CBP-0000-RevE-CAD-checkpoint006 (Autodesk Fusion 360 design; units mm, degrees)
part number: 2026-09-21-21-13-08-575
part number: 2026-09-22-14-43-03-767
part number: 2026-09-22-14-43-32-423
part number: 2026-09-22-14-58-32-491
part number: 2026-09-22-14-58-32-570
part number: 2026-09-22-14-58-32-641
part number: 2026-09-22-14-58-32-649
part number: 2026-09-22-14-58-32-656
part number: 2026-09-22-14-58-32-663
part number: 2026-09-22-14-58-32-671
part number: 2026-09-22-14-58-32-679
part number: 2026-09-22-14-58-32-687
part number: 2026-09-22-14-58-32-694
part number: 2026-09-22-14-58-32-777
part number: 2026-09-22-14-58-32-866
part number: 2026-09-22-15-02-12-520
part number: 2026-09-22-15-02-12-611
part number: 2026-09-22-15-02-12-705
part number: 2026-09-22-15-02-12-797
part number: 2026-09-22-15-02-12-894
part number: 2026-09-22-15-04-06-454
part number: 2026-09-22-15-34-02-991
part number: 2026-09-22-15-34-03-274
part number: 2026-09-22-15-34-03-552
Autodesk Fusion 360 part; units mm, degrees
(part 1 of 2)
sketch "SK-1100-01_BASE_OUTLINE_PARAMETRIC" plane through (0, 0, 0) normal (0, 1, 0) x (1, 0, 0) in component "CBP-1100_BASE_PLATE"
  line L0 (150, 130) -> (-150, 130)
  line L1 (-150, 130) -> (-150, -130)
  line L2 (-150, -130) -> (150, -130)
  line L3 (150, -130) -> (150, 130)
  line L4 (150, 130) -> (-150, -130) construction
  line L5 (-150, 130) -> (150, -130) construction
  dimension "d4" = 300
  dimension "d5" = 260
  constraint horizontal L0
  constraint perpendicular L0 L1
  constraint parallel L0 L2
  constraint parallel L1 L3
  constraint coincident L4 origin
  constraint coincident L5 origin
  measures "d4" distance of L0.start L0.end
  measures "d5" distance of L0 L2
extrude "EX-1100-01_BASE_STOCK" add sketch "SK-1100-01_BASE_OUTLINE_PARAMETRIC" along normal blind 12 makes body 1 in component "CBP-1100_BASE_PLATE"
sketch "SK-1100-02_CLEARANCE_APERTURE" plane through (0, 0, 0) normal (0, 1, 0) x (1, 0, 0) in component "CBP-1100_BASE_PLATE"
  line L0 (74, 49) -> (-74, 49)
  line L1 (-74, 49) -> (-74, -49)
  line L2 (-74, -49) -> (74, -49)
  line L3 (74, -49) -> (74, 49)
  dimension "d56" = 148
  dimension "d57" = 98
  dimension "d58" = 74
  dimension "d59" = 49
  constraint horizontal L0
  constraint vertical L1
  constraint horizontal L2
  constraint vertical L3
  measures "d56" horizontal distance of L0.start L0.end
  measures "d57" vertical distance of L0.end L1.end
  measures "d58" horizontal distance of origin L0.start
  measures "d59" vertical distance of origin L0.start
extrude "CUT-1100-01_BED_SWEEP_APERTURE" cut sketch "SK-1100-02_CLEARANCE_APERTURE" along normal blind 12 bodies 1 in component "CBP-1100_BASE_PLATE"
sketch "SK-1100-03_FOUR_BASE_MOUNTS" plane through (0, 0, 0) normal (0, 1, 0) x (1, 0, 0) in component "CBP-1100_BASE_PLATE"
  circle A0 centre (-130, -110) radius 4.5
  circle A1 centre (-130, 110) radius 4.5
  circle A2 centre (130, -110) radius 4.5
  circle A3 centre (130, 110) radius 4.5
  dimension "d62" = 130
  dimension "d63" = 110
  dimension "d64" = 9
  dimension "d65" = 110
  dimension "d66" = 130
  constraint vertical A0.centre A1.centre
  constraint equal A0 A1
  constraint horizontal A0.centre A2.centre
  constraint equal A0 A2
  constraint vertical A2.centre A3.centre
  constraint horizontal A1.centre A3.centre
  constraint equal A0 A3
  measures "d62" horizontal distance of origin A0.centre
  measures "d63" vertical distance of origin A0.centre
  measures "d64" diameter of A0
  measures "d65" vertical distance of origin A1.centre
  measures "d66" horizontal distance of origin A2.centre
extrude "CUT-1100-02_FOUR_M8_MOUNTS" cut sketch "SK-1100-03_FOUR_BASE_MOUNTS" along normal blind 12 bodies 1 in component "CBP-1100_BASE_PLATE"
sketch "SK-1200-01_COLUMN_SECTION" plane through (0, 0, 0) normal (0, 1, 0) x (1, 0, 0) in component "CBP-1200_40MM_Z_COLUMN"
  line L0 (20, 20) -> (-20, 20)
  line L1 (-20, 20) -> (-20, -20)
  line L2 (-20, -20) -> (20, -20)
  line L3 (20, -20) -> (20, 20)
  dimension "d69" = 40
  dimension "d70" = 40
  dimension "d71" = 20
  dimension "d72" = 20
  constraint horizontal L0
  constraint vertical L1
  constraint horizontal L2
  constraint vertical L3
  measures "d69" horizontal distance of L0.start L0.end
  measures "d70" vertical distance of L0.end L1.end
  measures "d71" horizontal distance of origin L0.start
  measures "d72" vertical distance of origin L0.start
extrude "EX-CBP-1200_COLUMN_ENVELOPE" add sketch "SK-1200-01_COLUMN_SECTION" along normal blind 180 separate body makes body 2 in component "CBP-1200_40MM_Z_COLUMN"
sketch "SK-1210-01_BEAM_SECTION" plane through (0, 0, 0) normal (0, 1, 0) x (1, 0, 0) in component "CBP-1210_Z_CROSSBEAM_ENVELOPE"
  line L0 (110, 20) -> (-110, 20)
  line L1 (-110, 20) -> (-110, -20)
  line L2 (-110, -20) -> (110, -20)
  line L3 (110, -20) -> (110, 20)
  dimension "d75" = 220
  dimension "d76" = 40
  dimension "d77" = 110
  dimension "d78" = 20
  constraint horizontal L0
  constraint vertical L1
  constraint horizontal L2
  constraint vertical L3
  measures "d75" horizontal distance of L0.start L0.end
  measures "d76" vertical distance of L0.end L1.end
  measures "d77" horizontal distance of origin L0.start
  measures "d78" vertical distance of origin L0.start
extrude "EX-CBP-1210_CROSSBEAM_ENVELOPE" add sketch "SK-1210-01_BEAM_SECTION" along normal blind 40 separate body makes body 3 in component "CBP-1210_Z_CROSSBEAM_ENVELOPE"
sketch "SK-2100-01_STAGE_OUTLINE" plane through (0, 0, 0) normal (0, 1, 0) x (1, 0, 0) in component "CBP-2100_CARBON_XY_STAGE"
  line L0 (56, 42) -> (-56, 42)
  line L1 (-56, 42) -> (-56, -42)
  line L2 (-56, -42) -> (56, -42)
  line L3 (56, -42) -> (56, 42)
  dimension "d81" = 112
  dimension "d82" = 84
  dimension "d83" = 56
  dimension "d84" = 42
  constraint horizontal L0
  constraint vertical L1
  constraint horizontal L2
  constraint vertical L3
  measures "d81" horizontal distance of L0.start L0.end
  measures "d82" vertical distance of L0.end L1.end
  measures "d83" horizontal distance of origin L0.start
  measures "d84" vertical distance of origin L0.start
extrude "EX-CBP-2100_2MM_STAGE_STOCK" add sketch "SK-2100-01_STAGE_OUTLINE" along normal blind 2 separate body makes body 4 in component "CBP-2100_CARBON_XY_STAGE"
sketch "SK-3100-01_BED_OUTLINE" plane through (0, 0, 0) normal (0, 1, 0) x (1, 0, 0) in component "CBP-3100_BED_SUBSTRATE"
  line L0 (38, 25) -> (-38, 25)
  line L1 (-38, 25) -> (-38, -25)
  line L2 (-38, -25) -> (38, -25)
  line L3 (38, -25) -> (38, 25)
  dimension "d87" = 76
  dimension "d88" = 50
  dimension "d89" = 38
  dimension "d90" = 25
  constraint horizontal L0
  constraint vertical L1
  constraint horizontal L2
  constraint vertical L3
  measures "d87" horizontal distance of L0.start L0.end
  measures "d88" vertical distance of L0.end L1.end
  measures "d89" horizontal distance of origin L0.start
  measures "d90" vertical distance of origin L0.start
extrude "EX-CBP-3100_BED_SUBSTRATE_STOCK" add sketch "SK-3100-01_BED_OUTLINE" along normal blind 3 separate body makes body 5 in component "CBP-3100_BED_SUBSTRATE"
sketch "SK-3110-01_SURFACE_OUTLINE" plane through (0, 0, 0) normal (0, 1, 0) x (1, 0, 0) in component "CBP-3110_BUILD_SURFACE"
  line L0 (38, 25) -> (-38, 25)
  line L1 (-38, 25) -> (-38, -25)
  line L2 (-38, -25) -> (38, -25)
  line L3 (38, -25) -> (38, 25)
  dimension "d93" = 76
  dimension "d94" = 50
  dimension "d95" = 38
  dimension "d96" = 25
  constraint horizontal L0
  constraint vertical L1
  constraint horizontal L2
  constraint vertical L3
  measures "d93" horizontal distance of L0.start L0.end
  measures "d94" vertical distance of L0.end L1.end
  measures "d95" horizontal distance of origin L0.start
  measures "d96" vertical distance of origin L0.start
extrude "EX-CBP-3110_BUILD_SURFACE_FILM" add sketch "SK-3110-01_SURFACE_OUTLINE" along normal blind 0.25 separate body makes body 6 in component "CBP-3110_BUILD_SURFACE"
sketch "SK-P201-01_X_RAIL_ENVELOPE" plane through (0, 0, 0) normal (0, 1, 0) x (1, 0, 0) in component "CBP-P201_MGN7_X_RAIL_130_PROXY"
  line L0 (65, 3.5) -> (-65, 3.5)
  line L1 (-65, 3.5) -> (-65, -3.5)
  line L2 (-65, -3.5) -> (65, -3.5)
  line L3 (65, -3.5) -> (65, 3.5)
  dimension "d110" = 130
  dimension "d111" = 7
  dimension "d112" = 65
  dimension "d113" = 3.5
  constraint horizontal L0
  constraint vertical L1
  constraint horizontal L2
  constraint vertical L3
  measures "d110" horizontal distance of L0.start L0.end
  measures "d111" vertical distance of L0.end L1.end
  measures "d112" horizontal distance of origin L0.start
  measures "d113" vertical distance of origin L0.start
extrude "EX-CBP-P201_X_RAIL_ENVELOPE" add sketch "SK-P201-01_X_RAIL_ENVELOPE" along normal blind 4.8 separate body makes body 7 in component "CBP-P201_MGN7_X_RAIL_130_PROXY"
sketch "SK-P202-01_X_BLOCK_CAP" plane through (0, 0, 0) normal (0, 1, 0) x (1, 0, 0) in component "CBP-P202_MGN7H_X_BLOCK_PROXY"
  line L0 (15.4, 8.5) -> (-15.4, 8.5)
  line L1 (-15.4, 8.5) -> (-15.4, -8.5)
  line L2 (-15.4, -8.5) -> (15.4, -8.5)
  line L3 (15.4, -8.5) -> (15.4, 8.5)
  dimension "d116" = 30.8
  dimension "d117" = 17
  dimension "d118" = 15.4
  dimension "d119" = 8.5
  constraint horizontal L0
  constraint vertical L1
  constraint horizontal L2
  constraint vertical L3
  measures "d116" horizontal distance of L0.start L0.end
  measures "d117" vertical distance of L0.end L1.end
  measures "d118" horizontal distance of origin L0.start
  measures "d119" vertical distance of origin L0.start
extrude "EX-CBP-P202_X_BLOCK_UPPER_ENVELOPE" add sketch "SK-P202-01_X_BLOCK_CAP" along normal blind 3.2 separate body makes body 8 in component "CBP-P202_MGN7H_X_BLOCK_PROXY"
sketch "SK-2200-01_BRIDGE_ENVELOPE" plane through (0, 0, 0) normal (0, 1, 0) x (1, 0, 0) in component "CBP-2200_CARBON_X_BRIDGE"
  line L0 (5, 70) -> (-5, 70)
  line L1 (-5, 70) -> (-5, -70)
  line L2 (-5, -70) -> (5, -70)
  line L3 (5, -70) -> (5, 70)
  dimension "d122" = 10
  dimension "d123" = 140
  dimension "d124" = 5
  dimension "d125" = 70
  constraint horizontal L0
  constraint vertical L1
  constraint horizontal L2
  constraint vertical L3
  measures "d122" horizontal distance of L0.start L0.end
  measures "d123" vertical distance of L0.end L1.end
  measures "d124" horizontal distance of origin L0.start
  measures "d125" vertical distance of origin L0.start
extrude "EX-CBP-2200_BRIDGE_STOCK" add sketch "SK-2200-01_BRIDGE_ENVELOPE" along normal blind 10 separate body makes body 9 in component "CBP-2200_CARBON_X_BRIDGE"
sketch "SK-P203-01_Y_RAIL_ENVELOPE" plane through (0, 0, 0) normal (0, 1, 0) x (1, 0, 0) in component "CBP-P203_MGN7_Y_RAIL_110_PROXY"
  line L0 (3.5, 55) -> (-3.5, 55)
  line L1 (-3.5, 55) -> (-3.5, -55)
  line L2 (-3.5, -55) -> (3.5, -55)
  line L3 (3.5, -55) -> (3.5, 55)
  dimension "d128" = 7
  dimension "d129" = 110
  dimension "d130" = 3.5
  dimension "d131" = 55
  constraint horizontal L0
  constraint vertical L1
  constraint horizontal L2
  constraint vertical L3
  measures "d128" horizontal distance of L0.start L0.end
  measures "d129" vertical distance of L0.end L1.end
  measures "d130" horizontal distance of origin L0.start
  measures "d131" vertical distance of origin L0.start
extrude "EX-CBP-P203_Y_RAIL_ENVELOPE" add sketch "SK-P203-01_Y_RAIL_ENVELOPE" along normal blind 4.8 separate body makes body 10 in component "CBP-P203_MGN7_Y_RAIL_110_PROXY"
sketch "SK-P204-01_Y_BLOCK_CAP" plane through (0, 0, 0) normal (0, 1, 0) x (1, 0, 0) in component "CBP-P204_MGN7H_Y_BLOCK_PROXY"
  line L0 (8.5, 15.4) -> (-8.5, 15.4)
  line L1 (-8.5, 15.4) -> (-8.5, -15.4)
  line L2 (-8.5, -15.4) -> (8.5, -15.4)
  line L3 (8.5, -15.4) -> (8.5, 15.4)
  dimension "d134" = 17
  dimension "d135" = 30.8
  dimension "d136" = 8.5
  dimension "d137" = 15.4
  constraint horizontal L0
  constraint vertical L1
  constraint horizontal L2
  constraint vertical L3
  measures "d134" horizontal distance of L0.start L0.end
  measures "d135" vertical distance of L0.end L1.end
  measures "d136" horizontal distance of origin L0.start
  measures "d137" vertical distance of origin L0.start
extrude "EX-CBP-P204_Y_BLOCK_UPPER_ENVELOPE" add sketch "SK-P204-01_Y_BLOCK_CAP" along normal blind 3.2 separate body makes body 11 in component "CBP-P204_MGN7H_Y_BLOCK_PROXY"
sketch "SK-1300-01_SHIM_OUTLINE" plane through (0, 0, 0) normal (0, 1, 0) x (1, 0, 0) in component "CBP-1300_X_RAIL_ALIGNMENT_SHIM"
  line L0 (65, 6) -> (-65, 6)
  line L1 (-65, 6) -> (-65, -6)
  line L2 (-65, -6) -> (65, -6)
  line L3 (65, -6) -> (65, 6)
  dimension "d142" = 130
  dimension "d143" = 12
  dimension "d144" = 65
  dimension "d145" = 6
  constraint horizontal L0
  constraint vertical L1
  constraint horizontal L2
  constraint vertical L3
  measures "d142" horizontal distance of L0.start L0.end
  measures "d143" vertical distance of L0.end L1.end
  measures "d144" horizontal distance of origin L0.start
  measures "d145" vertical distance of origin L0.start
extrude "EX-CBP-1300_SHIM_STOCK" add sketch "SK-1300-01_SHIM_OUTLINE" along normal blind 2 separate body makes body 12 in component "CBP-1300_X_RAIL_ALIGNMENT_SHIM"
sketch "SK-P201-02_NINE_MGN7_MOUNT_HOLES" plane through (0, 0, 0) normal (0, 1, 0) x (1, 0, 0) in component "CBP-P201_MGN7_X_RAIL_130_PROXY"
  circle A0 centre (-60, 0) radius 1.15
  circle A1 centre (-45, 0) radius 1.15
  circle A2 centre (-30, 0) radius 1.15
  circle A3 centre (-15, 0) radius 1.15
  circle A4 centre (0, 0) radius 1.15
  circle A5 centre (15, 0) radius 1.15
  circle A6 centre (30, 0) radius 1.15
  circle A7 centre (45, 0) radius 1.15
  circle A8 centre (60, 0) radius 1.15
  dimension "d151" = 60
  dimension "d152" = 2.3
  dimension "d153" = 45
  dimension "d154" = 2.3
  dimension "d155" = 30
  dimension "d156" = 2.3
  dimension "d157" = 15
  dimension "d158" = 2.3
  dimension "d159" = 2.3
  dimension "d160" = 15
  dimension "d161" = 2.3
  dimension "d162" = 30
  dimension "d163" = 2.3
  dimension "d164" = 45
  dimension "d165" = 2.3
  dimension "d166" = 60
  dimension "d167" = 2.3
  constraint horizontal A4.centre A0.centre
  constraint horizontal A4.centre A1.centre
  constraint horizontal A4.centre A2.centre
  constraint horizontal A4.centre A3.centre
  constraint coincident A4.centre origin
  constraint horizontal A4.centre A5.centre
  constraint horizontal A4.centre A6.centre
  constraint horizontal A4.centre A7.centre
  constraint horizontal A4.centre A8.centre
  measures "d151" horizontal distance of A4.centre A0.centre
  measures "d152" diameter of A0
  measures "d153" horizontal distance of A4.centre A1.centre
  measures "d154" diameter of A1
  measures "d155" horizontal distance of A4.centre A2.centre
  measures "d156" diameter of A2
  measures "d157" horizontal distance of A4.centre A3.centre
  measures "d158" diameter of A3
  measures "d159" diameter of A4
  measures "d160" horizontal distance of A4.centre A5.centre
  measures "d161" diameter of A5
  measures "d162" horizontal distance of A4.centre A6.centre
  measures "d163" diameter of A6
  measures "d164" horizontal distance of A4.centre A7.centre
  measures "d165" diameter of A7
  measures "d166" horizontal distance of A4.centre A8.centre
  measures "d167" diameter of A8
extrude "CUT-MGN7-THROUGH-HOLES" cut sketch "SK-P201-02_NINE_MGN7_MOUNT_HOLES" along normal blind 4.8 bodies 7 in component "CBP-P201_MGN7_X_RAIL_130_PROXY"
sketch "SK-P203-02_SEVEN_MGN7_MOUNT_HOLES" plane through (0, 0, 0) normal (0, 1, 0) x (1, 0, 0) in component "CBP-P203_MGN7_Y_RAIL_110_PROXY"
  circle A0 centre (0, -45) radius 1.15
  circle A1 centre (0, -30) radius 1.15
  circle A2 centre (0, -15) radius 1.15
  circle A3 centre (0, 0) radius 1.15
  circle A4 centre (0, 15) radius 1.15
  circle A5 centre (0, 30) radius 1.15
  circle A6 centre (0, 45) radius 1.15
  dimension "d170" = 45
  dimension "d171" = 2.3
  dimension "d172" = 30
  dimension "d173" = 2.3
  dimension "d174" = 15
  dimension "d175" = 2.3
  dimension "d176" = 2.3
  dimension "d177" = 15
  dimension "d178" = 2.3
  dimension "d179" = 30
  dimension "d180" = 2.3
  dimension "d181" = 45
  dimension "d182" = 2.3
  constraint vertical A3.centre A0.centre
  constraint vertical A3.centre A1.centre
  constraint vertical A3.centre A2.centre
  constraint coincident A3.centre origin
  constraint vertical A3.centre A4.centre
  constraint vertical A3.centre A5.centre
  constraint vertical A3.centre A6.centre
  measures "d170" vertical distance of A3.centre A0.centre
  measures "d171" diameter of A0
  measures "d172" vertical distance of A3.centre A1.centre
  measures "d173" diameter of A1
  measures "d174" vertical distance of A3.centre A2.centre
  measures "d175" diameter of A2
  measures "d176" diameter of A3
  measures "d177" vertical distance of A3.centre A4.centre
  measures "d178" diameter of A4
  measures "d179" vertical distance of A3.centre A5.centre
  measures "d180" diameter of A5
  measures "d181" vertical distance of A3.centre A6.centre
  measures "d182" diameter of A6
extrude "CUT-MGN7-THROUGH-HOLES'" cut sketch "SK-P203-02_SEVEN_MGN7_MOUNT_HOLES" along normal blind 4.8 bodies 10 in component "CBP-P203_MGN7_Y_RAIL_110_PROXY"
sketch "SK-P201-03_NINE_MGN7_COUNTERBORES" plane through (0, 4.8, 0) normal (0, 1, 0) x (0, 0, 1) in component "CBP-P201_MGN7_X_RAIL_130_PROXY"
  line L0 (3.5, 65) -> (-3.5, 65)
  line L1 (-3.5, 65) -> (-3.5, -65)
  line L2 (-3.5, -65) -> (3.5, -65)
  line L3 (3.5, -65) -> (3.5, 65)
  circle A0 centre (0, 60) radius 1.15
  circle A1 centre (0, 30) radius 1.15
  circle A2 centre (0, -60) radius 1.15
  circle A3 centre (0, -15) radius 1.15
  circle A4 centre (0, -45) radius 1.15
  circle A5 centre (0, -30) radius 1.15
  circle A6 centre (0, 0) radius 1.15
  circle A7 centre (0, 15) radius 1.15
  circle A8 centre (0, 45) radius 1.15
  circle A9 centre (0, -60) radius 2.1
  circle A10 centre (0, -45) radius 2.1
  circle A11 centre (0, -30) radius 2.1
  circle A12 centre (0, -15) radius 2.1
  circle A13 centre (0, 0) radius 2.1
  circle A14 centre (0, 15) radius 2.1
  circle A15 centre (0, 30) radius 2.1
  circle A16 centre (0, 45) radius 2.1
  circle A17 centre (0, 60) radius 2.1
  dimension "d187" = 60
  dimension "d188" = 4.2
  dimension "d189" = 45
  dimension "d190" = 4.2
  dimension "d191" = 30
  dimension "d192" = 4.2
  dimension "d193" = 15
  dimension "d194" = 4.2
  dimension "d195" = 4.2
  dimension "d196" = 15
  dimension "d197" = 4.2
  dimension "d198" = 30
  dimension "d199" = 4.2
  dimension "d200" = 45
  dimension "d201" = 4.2
  dimension "d202" = 60
  dimension "d203" = 4.2
  constraint vertical A6.centre A2.centre
  constraint vertical A6.centre A4.centre
  constraint vertical A6.centre A5.centre
  constraint vertical A6.centre A3.centre
  constraint coincident A6.centre A13.centre
  constraint vertical A6.centre A7.centre
  constraint vertical A6.centre A1.centre
  constraint vertical A6.centre A8.centre
  constraint vertical A6.centre A0.centre
  measures "d187" vertical distance of A6.centre A2.centre
  measures "d188" diameter of A9
  measures "d189" vertical distance of A6.centre A4.centre
  measures "d190" diameter of A10
  measures "d191" vertical distance of A6.centre A5.centre
  measures "d192" diameter of A11
  measures "d193" vertical distance of A6.centre A3.centre
  measures "d194" diameter of A12
  measures "d195" diameter of A13
  measures "d196" vertical distance of A6.centre A7.centre
  measures "d197" diameter of A14
  measures "d198" vertical distance of A6.centre A1.centre
  measures "d199" diameter of A15
  measures "d200" vertical distance of A6.centre A8.centre
  measures "d201" diameter of A16
  measures "d202" vertical distance of A6.centre A0.centre
  measures "d203" diameter of A17
sketch "SK-P203-03_SEVEN_MGN7_COUNTERBORES" plane through (0, 4.8, 0) normal (0, 1, 0) x (0, 0, 1) in component "CBP-P203_MGN7_Y_RAIL_110_PROXY"
  line L0 (55, 3.5) -> (-55, 3.5)
  line L1 (-55, 3.5) -> (-55, -3.5)
  line L2 (-55, -3.5) -> (55, -3.5)
  line L3 (55, -3.5) -> (55, 3.5)
  circle A0 centre (-45, 0) radius 1.15
  circle A1 centre (-15, 0) radius 1.15
  circle A2 centre (0, 0) radius 1.15
  circle A3 centre (30, 0) radius 1.15
  circle A4 centre (15, 0) radius 1.15
  circle A5 centre (45, 0) radius 1.15
  circle A6 centre (-30, 0) radius 1.15
  circle A7 centre (-45, 0) radius 2.1
  circle A8 centre (-30, 0) radius 2.1
  circle A9 centre (-15, 0) radius 2.1
  circle A10 centre (0, 0) radius 2.1
  circle A11 centre (15, 0) radius 2.1
  circle A12 centre (30, 0) radius 2.1
  circle A13 centre (45, 0) radius 2.1
  dimension "d206" = 45
  dimension "d207" = 4.2
  dimension "d208" = 30
  dimension "d209" = 4.2
  dimension "d210" = 15
  dimension "d211" = 4.2
  dimension "d212" = 4.2
  dimension "d213" = 15
  dimension "d214" = 4.2
  dimension "d215" = 30
  dimension "d216" = 4.2
  dimension "d217" = 45
  dimension "d218" = 4.2
  constraint horizontal A2.centre A0.centre
  constraint horizontal A2.centre A6.centre
  constraint horizontal A2.centre A1.centre
  constraint coincident A2.centre A10.centre
  constraint horizontal A2.centre A4.centre
  constraint horizontal A2.centre A3.centre
  constraint horizontal A2.centre A5.centre
  measures "d206" horizontal distance of A2.centre A0.centre
  measures "d207" diameter of A7
  measures "d208" horizontal distance of A2.centre A6.centre
  measures "d209" diameter of A8
  measures "d210" horizontal distance of A2.centre A1.centre
  measures "d211" diameter of A9
  measures "d212" diameter of A10
  measures "d213" horizontal distance of A2.centre A4.centre
  measures "d214" diameter of A11
  measures "d215" horizontal distance of A2.centre A3.centre
  measures "d216" diameter of A12
  measures "d217" horizontal distance of A2.centre A5.centre
  measures "d218" diameter of A13
extrude "CUT-MGN7-COUNTERBORES" cut sketch "SK-P201-03_NINE_MGN7_COUNTERBORES" against normal blind 2.4 contours A9 | A10 | A11 | A12 | A13 | A14 | A15 | A16 | A17 bodies 7 in component "CBP-P201_MGN7_X_RAIL_130_PROXY"
extrude "CUT-MGN7-COUNTERBORES'" cut sketch "SK-P203-03_SEVEN_MGN7_COUNTERBORES" against normal blind 2.4 contours A7 | A8 | A9 | A10 | A11 | A12 | A13 bodies 10 in component "CBP-P203_MGN7_Y_RAIL_110_PROXY"
sketch "SK-P202-02_FOUR_M2_PILOTS_01" plane through (0, 3.2, 0) normal (0, 1, 0) x (0, 0, 1) in component "CBP-P202_MGN7H_X_BLOCK_PROXY"
  line L0 (8.5, 15.4) -> (-8.5, 15.4)
  line L1 (-8.5, 15.4) -> (-8.5, -15.4)
  line L2 (-8.5, -15.4) -> (8.5, -15.4)
  line L3 (8.5, -15.4) -> (8.5, 15.4)
  circle A0 centre (-6, -6.5) radius 0.8
  dimension "d229" = 6
  dimension "d230" = 6.5
  dimension "d231" = 1.6
  measures "d229" horizontal distance of origin A0.centre
  measures "d230" vertical distance of origin A0.centre
  measures "d231" diameter of A0
extrude "CUT-MGN7H-M2-TAP-PILOT-01" cut sketch "SK-P202-02_FOUR_M2_PILOTS_01" against normal blind 2.5 contours A0 bodies 8 in component "CBP-P202_MGN7H_X_BLOCK_PROXY"
sketch "SK-P202-02_FOUR_M2_PILOTS_02" plane through (0, 3.2, 0) normal (0, 1, 0) x (0, 0, 1) in component "CBP-P202_MGN7H_X_BLOCK_PROXY"
  circle A0 centre (-6, -6.5) radius 0.8
  line L0 (8.5, 15.4) -> (-8.5, 15.4)
  line L1 (-8.5, 15.4) -> (-8.5, -15.4)
  line L2 (-8.5, -15.4) -> (8.5, -15.4)
  line L3 (8.5, -15.4) -> (8.5, 15.4)
  circle A1 centre (6, -6.5) radius 0.8
  dimension "d234" = 6
  dimension "d235" = 6.5
  dimension "d236" = 1.6
  measures "d234" horizontal distance of origin A1.centre
  measures "d235" vertical distance of origin A1.centre
  measures "d236" diameter of A1
extrude "CUT-MGN7H-M2-TAP-PILOT-02" cut sketch "SK-P202-02_FOUR_M2_PILOTS_02" against normal blind 2.5 contours A1 bodies 8 in component "CBP-P202_MGN7H_X_BLOCK_PROXY"
sketch "SK-P202-02_FOUR_M2_PILOTS_03" plane through (0, 3.2, 0) normal (0, 1, 0) x (0, 0, 1) in component "CBP-P202_MGN7H_X_BLOCK_PROXY"
  circle A0 centre (6, -6.5) radius 0.8
  circle A1 centre (-6, -6.5) radius 0.8
  line L0 (8.5, 15.4) -> (-8.5, 15.4)
  line L1 (-8.5, 15.4) -> (-8.5, -15.4)
  line L2 (-8.5, -15.4) -> (8.5, -15.4)
  line L3 (8.5, -15.4) -> (8.5, 15.4)
  circle A2 centre (-6, 6.5) radius 0.8
  dimension "d239" = 6
  dimension "d240" = 6.5
  dimension "d241" = 1.6
  measures "d239" horizontal distance of origin A2.centre
  measures "d240" vertical distance of origin A2.centre
  measures "d241" diameter of A2
extrude "CUT-MGN7H-M2-TAP-PILOT-03" cut sketch "SK-P202-02_FOUR_M2_PILOTS_03" against normal blind 2.5 contours A2 bodies 8 in component "CBP-P202_MGN7H_X_BLOCK_PROXY"
sketch "SK-P202-02_FOUR_M2_PILOTS_04" plane through (0, 3.2, 0) normal (0, 1, 0) x (0, 0, 1) in component "CBP-P202_MGN7H_X_BLOCK_PROXY"
  circle A0 centre (-6, 6.5) radius 0.8
  circle A1 centre (6, -6.5) radius 0.8
  circle A2 centre (-6, -6.5) radius 0.8
  line L0 (8.5, 15.4) -> (-8.5, 15.4)
  line L1 (-8.5, 15.4) -> (-8.5, -15.4)
  line L2 (-8.5, -15.4) -> (8.5, -15.4)
  line L3 (8.5, -15.4) -> (8.5, 15.4)
  circle A3 centre (6, 6.5) radius 0.8
  dimension "d244" = 6
  dimension "d245" = 6.5
  dimension "d246" = 1.6
  measures "d244" horizontal distance of origin A3.centre
  measures "d245" vertical distance of origin A3.centre
  measures "d246" diameter of A3
extrude "CUT-MGN7H-M2-TAP-PILOT-04" cut sketch "SK-P202-02_FOUR_M2_PILOTS_04" against normal blind 2.5 contours A3 bodies 8 in component "CBP-P202_MGN7H_X_BLOCK_PROXY"
sketch "SK-P204-02_FOUR_M2_PILOTS_01" plane through (0, 3.2, 0) normal (0, 1, 0) x (0, 0, 1) in component "CBP-P204_MGN7H_Y_BLOCK_PROXY"
  line L0 (15.4, 8.5) -> (-15.4, 8.5)
  line L1 (-15.4, 8.5) -> (-15.4, -8.5)
  line L2 (-15.4, -8.5) -> (15.4, -8.5)
  line L3 (15.4, -8.5) -> (15.4, 8.5)
  circle A0 centre (-6.5, -6) radius 0.8
  dimension "d249" = 6.5
  dimension "d250" = 6
  dimension "d251" = 1.6
  measures "d249" horizontal distance of origin A0.centre
  measures "d250" vertical distance of origin A0.centre
  measures "d251" diameter of A0
extrude "CUT-MGN7H-M2-TAP-PILOT-01'" cut sketch "SK-P204-02_FOUR_M2_PILOTS_01" against normal blind 2.5 contours A0 bodies 11 in component "CBP-P204_MGN7H_Y_BLOCK_PROXY"
sketch "SK-P204-02_FOUR_M2_PILOTS_02" plane through (0, 3.2, 0) normal (0, 1, 0) x (0, 0, 1) in component "CBP-P204_MGN7H_Y_BLOCK_PROXY"
  circle A0 centre (-6.5, -6) radius 0.8
  line L0 (15.4, 8.5) -> (-15.4, 8.5)
  line L1 (-15.4, 8.5) -> (-15.4, -8.5)
  line L2 (-15.4, -8.5) -> (15.4, -8.5)
  line L3 (15.4, -8.5) -> (15.4, 8.5)
  circle A1 centre (6.5, -6) radius 0.8
  dimension "d254" = 6.5
  dimension "d255" = 6
  dimension "d256" = 1.6
  measures "d254" horizontal distance of origin A1.centre
  measures "d255" vertical distance of origin A1.centre
  measures "d256" diameter of A1
extrude "CUT-MGN7H-M2-TAP-PILOT-02'" cut sketch "SK-P204-02_FOUR_M2_PILOTS_02" against normal blind 2.5 contours A1 bodies 11 in component "CBP-P204_MGN7H_Y_BLOCK_PROXY"
sketch "SK-P204-02_FOUR_M2_PILOTS_03" plane through (0, 3.2, 0) normal (0, 1, 0) x (0, 0, 1) in component "CBP-P204_MGN7H_Y_BLOCK_PROXY"
  circle A0 centre (6.5, -6) radius 0.8
  circle A1 centre (-6.5, -6) radius 0.8
  line L0 (15.4, 8.5) -> (-15.4, 8.5)
  line L1 (-15.4, 8.5) -> (-15.4, -8.5)
  line L2 (-15.4, -8.5) -> (15.4, -8.5)
  line L3 (15.4, -8.5) -> (15.4, 8.5)
  circle A2 centre (-6.5, 6) radius 0.8
  dimension "d259" = 6.5
  dimension "d260" = 6
  dimension "d261" = 1.6
  measures "d259" horizontal distance of origin A2.centre
  measures "d260" vertical distance of origin A2.centre
  measures "d261" diameter of A2
extrude "CUT-MGN7H-M2-TAP-PILOT-03'" cut sketch "SK-P204-02_FOUR_M2_PILOTS_03" against normal blind 2.5 contours A2 bodies 11 in component "CBP-P204_MGN7H_Y_BLOCK_PROXY"
sketch "SK-P204-02_FOUR_M2_PILOTS_04" plane through (0, 3.2, 0) normal (0, 1, 0) x (0, 0, 1) in component "CBP-P204_MGN7H_Y_BLOCK_PROXY"
  circle A0 centre (-6.5, 6) radius 0.8
  circle A1 centre (6.5, -6) radius 0.8
  circle A2 centre (-6.5, -6) radius 0.8
  line L0 (15.4, 8.5) -> (-15.4, 8.5)
  line L1 (-15.4, 8.5) -> (-15.4, -8.5)
  line L2 (-15.4, -8.5) -> (15.4, -8.5)
  line L3 (15.4, -8.5) -> (15.4, 8.5)
  circle A3 centre (6.5, 6) radius 0.8
  dimension "d264" = 6.5
  dimension "d265" = 6
  dimension "d266" = 1.6
  measures "d264" horizontal distance of origin A3.centre
  measures "d265" vertical distance of origin A3.centre
  measures "d266" diameter of A3
extrude "CUT-MGN7H-M2-TAP-PILOT-04'" cut sketch "SK-P204-02_FOUR_M2_PILOTS_04" against normal blind 2.5 contours A3 bodies 11 in component "CBP-P204_MGN7H_Y_BLOCK_PROXY"
sketch "SK-2200-02_END_PAD_A" plane through (0, 0, 0) normal (0, 1, 0) x (1, 0, 0) in component "CBP-2200_CARBON_X_BRIDGE"
  line L0 (11, -72) -> (-11, -72)
  line L1 (-11, -72) -> (-11, -48)
  line L2 (-11, -48) -> (11, -48)
  line L3 (11, -48) -> (11, -72)
  dimension "d271" = 22
  dimension "d272" = 24
  dimension "d273" = 11
  dimension "d274" = 72
  constraint horizontal L0
  constraint vertical L1
  constraint horizontal L2
  constraint vertical L3
  measures "d271" horizontal distance of L0.start L0.end
  measures "d272" vertical distance of L0.end L1.end
  measures "d273" horizontal distance of origin L0.start
  measures "d274" vertical distance of origin L0.start
extrude "JOIN-BRIDGE-END-PAD-A" add sketch "SK-2200-02_END_PAD_A" along normal blind 10 bodies 9 in component "CBP-2200_CARBON_X_BRIDGE"
sketch "SK-2200-02_END_PAD_B" plane through (0, 0, 0) normal (0, 1, 0) x (1, 0, 0) in component "CBP-2200_CARBON_X_BRIDGE"
  line L0 (11, 72) -> (-11, 72)
  line L1 (-11, 72) -> (-11, 48)
  line L2 (-11, 48) -> (11, 48)
  line L3 (11, 48) -> (11, 72)
  dimension "d277" = 22
  dimension "d278" = 24
  dimension "d279" = 11
  dimension "d280" = 72
  constraint horizontal L0
  constraint vertical L1
  constraint horizontal L2
  constraint vertical L3
  measures "d277" horizontal distance of L0.start L0.end
  measures "d278" vertical distance of L0.end L1.end
  measures "d279" horizontal distance of origin L0.start
  measures "d280" vertical distance of origin L0.start
extrude "JOIN-BRIDGE-END-PAD-B" add sketch "SK-2200-02_END_PAD_B" along normal blind 10 bodies 9 in component "CBP-2200_CARBON_X_BRIDGE"
sketch "SK-2200-03_M2_XBLOCK_CLEAR_01" plane through (0, 0, 0) normal (0, 1, 0) x (1, 0, 0) in component "CBP-2200_CARBON_X_BRIDGE"
  circle A0 centre (-6.5, -66) radius 1.1
  dimension "d284" = 6.5
  dimension "d285" = 66
  dimension "d286" = 2.2
  measures "d284" horizontal distance of origin A0.centre
  measures "d285" vertical distance of origin A0.centre
  measures "d286" diameter of A0
extrude "CUT-M2-CARRIAGE-CLEAR-01" cut sketch "SK-2200-03_M2_XBLOCK_CLEAR_01" along normal blind 10 bodies 9 in component "CBP-2200_CARBON_X_BRIDGE"
sketch "SK-2200-03_M2_XBLOCK_CLEAR_02" plane through (0, 0, 0) normal (0, 1, 0) x (1, 0, 0) in component "CBP-2200_CARBON_X_BRIDGE"
  circle A0 centre (-6.5, -54) radius 1.1
  dimension "d289" = 6.5
  dimension "d290" = 54
  dimension "d291" = 2.2
  measures "d289" horizontal distance of origin A0.centre
  measures "d290" vertical distance of origin A0.centre
  measures "d291" diameter of A0
extrude "CUT-M2-CARRIAGE-CLEAR-02" cut sketch "SK-2200-03_M2_XBLOCK_CLEAR_02" along normal blind 10 bodies 9 in component "CBP-2200_CARBON_X_BRIDGE"
sketch "SK-2200-03_M2_XBLOCK_CLEAR_03" plane through (0, 0, 0) normal (0, 1, 0) x (1, 0, 0) in component "CBP-2200_CARBON_X_BRIDGE"
  circle A0 centre (6.5, -66) radius 1.1
  dimension "d294" = 6.5
  dimension "d295" = 66
  dimension "d296" = 2.2
  measures "d294" horizontal distance of origin A0.centre
  measures "d295" vertical distance of origin A0.centre
  measures "d296" diameter of A0
extrude "CUT-M2-CARRIAGE-CLEAR-03" cut sketch "SK-2200-03_M2_XBLOCK_CLEAR_03" along normal blind 10 bodies 9 in component "CBP-2200_CARBON_X_BRIDGE"
sketch "SK-2200-03_M2_XBLOCK_CLEAR_04" plane through (0, 0, 0) normal (0, 1, 0) x (1, 0, 0) in component "CBP-2200_CARBON_X_BRIDGE"
  circle A0 centre (6.5, -54) radius 1.1
  dimension "d299" = 6.5
  dimension "d300" = 54
  dimension "d301" = 2.2
  measures "d299" horizontal distance of origin A0.centre
  measures "d300" vertical distance of origin A0.centre
  measures "d301" diameter of A0
extrude "CUT-M2-CARRIAGE-CLEAR-04" cut sketch "SK-2200-03_M2_XBLOCK_CLEAR_04" along normal blind 10 bodies 9 in component "CBP-2200_CARBON_X_BRIDGE"
sketch "SK-2200-03_M2_XBLOCK_CLEAR_05" plane through (0, 0, 0) normal (0, 1, 0) x (1, 0, 0) in component "CBP-2200_CARBON_X_BRIDGE"
  circle A0 centre (-6.5, 54) radius 1.1
  dimension "d304" = 6.5
  dimension "d305" = 54
  dimension "d306" = 2.2
  measures "d304" horizontal distance of origin A0.centre
  measures "d305" vertical distance of origin A0.centre
  measures "d306" diameter of A0
extrude "CUT-M2-CARRIAGE-CLEAR-05" cut sketch "SK-2200-03_M2_XBLOCK_CLEAR_05" along normal blind 10 bodies 9 in component "CBP-2200_CARBON_X_BRIDGE"
sketch "SK-2200-03_M2_XBLOCK_CLEAR_06" plane through (0, 0, 0) normal (0, 1, 0) x (1, 0, 0) in component "CBP-2200_CARBON_X_BRIDGE"
  circle A0 centre (-6.5, 66) radius 1.1
  dimension "d309" = 6.5
  dimension "d310" = 66
  dimension "d311" = 2.2
  measures "d309" horizontal distance of origin A0.centre
  measures "d310" vertical distance of origin A0.centre
  measures "d311" diameter of A0
extrude "CUT-M2-CARRIAGE-CLEAR-06" cut sketch "SK-2200-03_M2_XBLOCK_CLEAR_06" along normal blind 10 bodies 9 in component "CBP-2200_CARBON_X_BRIDGE"
sketch "SK-2200-03_M2_XBLOCK_CLEAR_07" plane through (0, 0, 0) normal (0, 1, 0) x (1, 0, 0) in component "CBP-2200_CARBON_X_BRIDGE"
  circle A0 centre (6.5, 54) radius 1.1
  dimension "d314" = 6.5
  dimension "d315" = 54
  dimension "d316" = 2.2
  measures "d314" horizontal distance of origin A0.centre
  measures "d315" vertical distance of origin A0.centre
  measures "d316" diameter of A0
extrude "CUT-M2-CARRIAGE-CLEAR-07" cut sketch "SK-2200-03_M2_XBLOCK_CLEAR_07" along normal blind 10 bodies 9 in component "CBP-2200_CARBON_X_BRIDGE"
sketch "SK-2200-03_M2_XBLOCK_CLEAR_08" plane through (0, 0, 0) normal (0, 1, 0) x (1, 0, 0) in component "CBP-2200_CARBON_X_BRIDGE"
  circle A0 centre (6.5, 66) radius 1.1
  dimension "d319" = 6.5
  dimension "d320" = 66
  dimension "d321" = 2.2
  measures "d319" horizontal distance of origin A0.centre
  measures "d320" vertical distance of origin A0.centre
  measures "d321" diameter of A0
extrude "CUT-M2-CARRIAGE-CLEAR-08" cut sketch "SK-2200-03_M2_XBLOCK_CLEAR_08" along normal blind 10 bodies 9 in component "CBP-2200_CARBON_X_BRIDGE"
sketch "SK-2100-02_M2_YBLOCK_CLEAR_01" plane through (0, 0, 0) normal (0, 1, 0) x (1, 0, 0) in component "CBP-2100_CARBON_XY_STAGE"
  circle A0 centre (-6, -6.5) radius 1.1
  dimension "d324" = 6
  dimension "d325" = 6.5
  dimension "d326" = 2.2
  measures "d324" horizontal distance of origin A0.centre
  measures "d325" vertical distance of origin A0.centre
  measures "d326" diameter of A0
extrude "CUT-M2-CARRIAGE-CLEAR-01'" cut sketch "SK-2100-02_M2_YBLOCK_CLEAR_01" along normal blind 2 bodies 4 in component "CBP-2100_CARBON_XY_STAGE"
sketch "SK-2100-02_M2_YBLOCK_CLEAR_02" plane through (0, 0, 0) normal (0, 1, 0) x (1, 0, 0) in component "CBP-2100_CARBON_XY_STAGE"
  circle A0 centre (-6, 6.5) radius 1.1
  dimension "d329" = 6
  dimension "d330" = 6.5
  dimension "d331" = 2.2
  measures "d329" horizontal distance of origin A0.centre
  measures "d330" vertical distance of origin A0.centre
  measures "d331" diameter of A0
extrude "CUT-M2-CARRIAGE-CLEAR-02'" cut sketch "SK-2100-02_M2_YBLOCK_CLEAR_02" along normal blind 2 bodies 4 in component "CBP-2100_CARBON_XY_STAGE"
sketch "SK-2100-02_M2_YBLOCK_CLEAR_03" plane through (0, 0, 0) normal (0, 1, 0) x (1, 0, 0) in component "CBP-2100_CARBON_XY_STAGE"
  circle A0 centre (6, -6.5) radius 1.1
  dimension "d334" = 6
  dimension "d335" = 6.5
  dimension "d336" = 2.2
  measures "d334" horizontal distance of origin A0.centre
  measures "d335" vertical distance of origin A0.centre
  measures "d336" diameter of A0
extrude "CUT-M2-CARRIAGE-CLEAR-03'" cut sketch "SK-2100-02_M2_YBLOCK_CLEAR_03" along normal blind 2 bodies 4 in component "CBP-2100_CARBON_XY_STAGE"
sketch "SK-2100-02_M2_YBLOCK_CLEAR_04" plane through (0, 0, 0) normal (0, 1, 0) x (1, 0, 0) in component "CBP-2100_CARBON_XY_STAGE"
  circle A0 centre (6, 6.5) radius 1.1
  dimension "d339" = 6
  dimension "d340" = 6.5
  dimension "d341" = 2.2
  measures "d339" horizontal distance of origin A0.centre
  measures "d340" vertical distance of origin A0.centre
  measures "d341" diameter of A0
extrude "CUT-M2-CARRIAGE-CLEAR-04'" cut sketch "SK-2100-02_M2_YBLOCK_CLEAR_04" along normal blind 2 bodies 4 in component "CBP-2100_CARBON_XY_STAGE"
sketch "SK-2200-04_M2_YRAIL_CLEAR_01" plane through (0, 0, 0) normal (0, 1, 0) x (1, 0, 0) in component "CBP-2200_CARBON_X_BRIDGE"
  circle A0 centre (0, -45) radius 1.1
  dimension "d344" = 45
  dimension "d345" = 2.2
  constraint vertical origin A0.centre
  measures "d344" vertical distance of origin A0.centre
  measures "d345" diameter of A0
extrude "CUT-M2-CARRIAGE-CLEAR-01 (1)" cut sketch "SK-2200-04_M2_YRAIL_CLEAR_01" along normal blind 10 bodies 9 in component "CBP-2200_CARBON_X_BRIDGE"
sketch "SK-2200-04_M2_YRAIL_CLEAR_02" plane through (0, 0, 0) normal (0, 1, 0) x (1, 0, 0) in component "CBP-2200_CARBON_X_BRIDGE"
  circle A0 centre (0, -30) radius 1.1
  dimension "d348" = 30
  dimension "d349" = 2.2
  constraint vertical origin A0.centre
  measures "d348" vertical distance of origin A0.centre
  measures "d349" diameter of A0
extrude "CUT-M2-CARRIAGE-CLEAR-02 (1)" cut sketch "SK-2200-04_M2_YRAIL_CLEAR_02" along normal blind 10 bodies 9 in component "CBP-2200_CARBON_X_BRIDGE"
sketch "SK-2200-04_M2_YRAIL_CLEAR_03" plane through (0, 0, 0) normal (0, 1, 0) x (1, 0, 0) in component "CBP-2200_CARBON_X_BRIDGE"
  circle A0 centre (0, -15) radius 1.1
  dimension "d352" = 15
  dimension "d353" = 2.2
  constraint vertical origin A0.centre
  measures "d352" vertical distance of origin A0.centre
  measures "d353" diameter of A0
extrude "CUT-M2-CARRIAGE-CLEAR-03 (1)" cut sketch "SK-2200-04_M2_YRAIL_CLEAR_03" along normal blind 10 bodies 9 in component "CBP-2200_CARBON_X_BRIDGE"
sketch "SK-2200-04_M2_YRAIL_CLEAR_04" plane through (0, 0, 0) normal (0, 1, 0) x (1, 0, 0) in component "CBP-2200_CARBON_X_BRIDGE"
  circle A0 centre (0, 0) radius 1.1
  dimension "d356" = 2.2
  constraint coincident A0.centre origin
  measures "d356" diameter of A0
extrude "CUT-M2-CARRIAGE-CLEAR-04 (1)" cut sketch "SK-2200-04_M2_YRAIL_CLEAR_04" along normal blind 10 bodies 9 in component "CBP-2200_CARBON_X_BRIDGE"
sketch "SK-2200-04_M2_YRAIL_CLEAR_05" plane through (0, 0, 0) normal (0, 1, 0) x (1, 0, 0) in component "CBP-2200_CARBON_X_BRIDGE"
  circle A0 centre (0, 15) radius 1.1
  dimension "d359" = 15
  dimension "d360" = 2.2
  constraint vertical origin A0.centre
  measures "d359" vertical distance of origin A0.centre
  measures "d360" diameter of A0
extrude "CUT-M2-CARRIAGE-CLEAR-05 (1)" cut sketch "SK-2200-04_M2_YRAIL_CLEAR_05" along normal blind 10 bodies 9 in component "CBP-2200_CARBON_X_BRIDGE"
sketch "SK-2200-04_M2_YRAIL_CLEAR_06" plane through (0, 0, 0) normal (0, 1, 0) x (1, 0, 0) in component "CBP-2200_CARBON_X_BRIDGE"
  circle A0 centre (0, 30) radius 1.1
  dimension "d363" = 30
  dimension "d364" = 2.2
  constraint vertical origin A0.centre
  measures "d363" vertical distance of origin A0.centre
  measures "d364" diameter of A0
extrude "CUT-M2-CARRIAGE-CLEAR-06 (1)" cut sketch "SK-2200-04_M2_YRAIL_CLEAR_06" along normal blind 10 bodies 9 in component "CBP-2200_CARBON_X_BRIDGE"
sketch "SK-2200-04_M2_YRAIL_CLEAR_07" plane through (0, 0, 0) normal (0, 1, 0) x (1, 0, 0) in component "CBP-2200_CARBON_X_BRIDGE"
  circle A0 centre (0, 45) radius 1.1
  dimension "d367" = 45
  dimension "d368" = 2.2
  constraint vertical origin A0.centre
  measures "d367" vertical distance of origin A0.centre
  measures "d368" diameter of A0
extrude "CUT-M2-CARRIAGE-CLEAR-07 (1)" cut sketch "SK-2200-04_M2_YRAIL_CLEAR_07" along normal blind 10 bodies 9 in component "CBP-2200_CARBON_X_BRIDGE"
sketch "SK-1300-02_RAIL_CLEAR_01" plane through (0, 0, 0) normal (0, 1, 0) x (1, 0, 0) in component "CBP-1300_X_RAIL_ALIGNMENT_SHIM"
  circle A0 centre (-60, 0) radius 1.15
  dimension "d373" = 60
  dimension "d374" = 2.3
  constraint horizontal origin A0.centre
  measures "d373" horizontal distance of origin A0.centre
  measures "d374" diameter of A0
extrude "CUT-SK-1300-02_RAIL_CLEAR_01" cut sketch "SK-1300-02_RAIL_CLEAR_01" along normal blind 2 bodies 12 in component "CBP-1300_X_RAIL_ALIGNMENT_SHIM"
sketch "SK-1100-04_M2_RAIL_TAP_A01" plane through (0, 12, 0) normal (0, 1, 0) x (0, 0, 1) in component "CBP-1100_BASE_PLATE"
  line L0 (130, 150) -> (-130, 150)
  line L1 (-130, 150) -> (-130, -150)
  line L2 (-130, -150) -> (130, -150)
  line L3 (130, -150) -> (130, 150)
  line L4 (49, 74) -> (49, -74)
  line L5 (49, -74) -> (-49, -74)
  line L6 (-49, -74) -> (-49, 74)
  line L7 (-49, 74) -> (49, 74)
  circle A0 centre (-110, 130) radius 4.5
  circle A1 centre (110, -130) radius 4.5
  circle A2 centre (-110, -130) radius 4.5
  circle A3 centre (110, 130) radius 4.5
  circle A4 centre (-60, -60) radius 0.8
  dimension "d377" = 60
  dimension "d378" = 60
  dimension "d379" = 1.6
  measures "d377" horizontal distance of origin A4.centre
  measures "d378" vertical distance of origin A4.centre
  measures "d379" diameter of A4
extrude "CUT-SK-1100-04_M2_RAIL_TAP_A01" cut sketch "SK-1100-04_M2_RAIL_TAP_A01" against normal blind 4 contours A4 bodies 1 in component "CBP-1100_BASE_PLATE"
sketch "SK-1100-04_M2_RAIL_TAP_B01" plane through (0, 12, 0) normal (0, 1, 0) x (0, 0, 1) in component "CBP-1100_BASE_PLATE"
  circle A0 centre (-60, -60) radius 0.8
  line L0 (130, 150) -> (-130, 150)
  line L1 (-130, 150) -> (-130, -150)
  line L2 (-130, -150) -> (130, -150)
  line L3 (130, -150) -> (130, 150)
  line L4 (49, 74) -> (49, -74)
  line L5 (49, -74) -> (-49, -74)
  line L6 (-49, -74) -> (-49, 74)
  line L7 (-49, 74) -> (49, 74)
  circle A1 centre (-110, 130) radius 4.5
  circle A2 centre (110, -130) radius 4.5
  circle A3 centre (-110, -130) radius 4.5
  circle A4 centre (110, 130) radius 4.5
  circle A5 centre (60, -60) radius 0.8
  dimension "d382" = 60
  dimension "d383" = 60
  dimension "d384" = 1.6
  measures "d382" horizontal distance of origin A5.centre
  measures "d383" vertical distance of origin A5.centre
  measures "d384" diameter of A5
extrude "CUT-SK-1100-04_M2_RAIL_TAP_B01" cut sketch "SK-1100-04_M2_RAIL_TAP_B01" against normal blind 4 contours A5 bodies 1 in component "CBP-1100_BASE_PLATE"
sketch "SK-1300-02_RAIL_CLEAR_02" plane through (0, 0, 0) normal (0, 1, 0) x (1, 0, 0) in component "CBP-1300_X_RAIL_ALIGNMENT_SHIM"
  circle A0 centre (-45, 0) radius 1.15
  dimension "d387" = 45
  dimension "d388" = 2.3
  constraint horizontal origin A0.centre
  measures "d387" horizontal distance of origin A0.centre
  measures "d388" diameter of A0
extrude "CUT-SK-1300-02_RAIL_CLEAR_02" cut sketch "SK-1300-02_RAIL_CLEAR_02" along normal blind 2 bodies 12 in component "CBP-1300_X_RAIL_ALIGNMENT_SHIM"
sketch "SK-1100-04_M2_RAIL_TAP_A02" plane through (0, 12, 0) normal (0, 1, 0) x (0, 0, 1) in component "CBP-1100_BASE_PLATE"
  circle A0 centre (60, -60) radius 0.8
  circle A1 centre (-60, -60) radius 0.8
  line L0 (130, 150) -> (-130, 150)
  line L1 (-130, 150) -> (-130, -150)
  line L2 (-130, -150) -> (130, -150)
  line L3 (130, -150) -> (130, 150)
  line L4 (49, 74) -> (49, -74)
  line L5 (49, -74) -> (-49, -74)
  line L6 (-49, -74) -> (-49, 74)
  line L7 (-49, 74) -> (49, 74)
  circle A2 centre (-110, 130) radius 4.5
  circle A3 centre (110, -130) radius 4.5
  circle A4 centre (-110, -130) radius 4.5
  circle A5 centre (110, 130) radius 4.5
  circle A6 centre (-60, -45) radius 0.8
  dimension "d391" = 60
  dimension "d392" = 45
  dimension "d393" = 1.6
  measures "d391" horizontal distance of origin A6.centre
  measures "d392" vertical distance of origin A6.centre
  measures "d393" diameter of A6
extrude "CUT-SK-1100-04_M2_RAIL_TAP_A02" cut sketch "SK-1100-04_M2_RAIL_TAP_A02" against normal blind 4 contours A6 bodies 1 in component "CBP-1100_BASE_PLATE"
sketch "SK-1100-04_M2_RAIL_TAP_B02" plane through (0, 12, 0) normal (0, 1, 0) x (0, 0, 1) in component "CBP-1100_BASE_PLATE"
  circle A0 centre (110, 130) radius 4.5
  circle A1 centre (-110, -130) radius 4.5
  circle A2 centre (110, -130) radius 4.5
  circle A3 centre (-110, 130) radius 4.5
  line L0 (49, 74) -> (49, -74)
  line L1 (49, -74) -> (-49, -74)
  line L2 (-49, -74) -> (-49, 74)
  line L3 (-49, 74) -> (49, 74)
  line L4 (130, 150) -> (-130, 150)
  line L5 (-130, 150) -> (-130, -150)
  line L6 (-130, -150) -> (130, -150)
  line L7 (130, -150) -> (130, 150)
  circle A4 centre (-60, -60) radius 0.8
  circle A5 centre (60, -60) radius 0.8
  circle A6 centre (-60, -45) radius 0.8
  circle A7 centre (60, -45) radius 0.8
  dimension "d396" = 60
  dimension "d397" = 45
  dimension "d398" = 1.6
  measures "d396" horizontal distance of origin A7.centre
  measures "d397" vertical distance of origin A7.centre
  measures "d398" diameter of A7
extrude "CUT-SK-1100-04_M2_RAIL_TAP_B02" cut sketch "SK-1100-04_M2_RAIL_TAP_B02" against normal blind 4 contours A7 bodies 1 in component "CBP-1100_BASE_PLATE"
sketch "SK-1300-02_RAIL_CLEAR_03" plane through (0, 0, 0) normal (0, 1, 0) x (1, 0, 0) in component "CBP-1300_X_RAIL_ALIGNMENT_SHIM"
  circle A0 centre (-30, 0) radius 1.15
  dimension "d401" = 30
  dimension "d402" = 2.3
  constraint horizontal origin A0.centre
  measures "d401" horizontal distance of origin A0.centre
  measures "d402" diameter of A0
extrude "CUT-SK-1300-02_RAIL_CLEAR_03" cut sketch "SK-1300-02_RAIL_CLEAR_03" along normal blind 2 bodies 12 in component "CBP-1300_X_RAIL_ALIGNMENT_SHIM"
sketch "SK-1100-04_M2_RAIL_TAP_A03" plane through (0, 12, 0) normal (0, 1, 0) x (0, 0, 1) in component "CBP-1100_BASE_PLATE"
  circle A0 centre (-60, -45) radius 0.8
  circle A1 centre (60, -60) radius 0.8
  circle A2 centre (-60, -60) radius 0.8
  line L0 (130, 150) -> (-130, 150)
  line L1 (-130, 150) -> (-130, -150)
  line L2 (-130, -150) -> (130, -150)
  line L3 (130, -150) -> (130, 150)
  line L4 (49, 74) -> (49, -74)
  line L5 (49, -74) -> (-49, -74)
  line L6 (-49, -74) -> (-49, 74)
  line L7 (-49, 74) -> (49, 74)
  circle A3 centre (-110, 130) radius 4.5
  circle A4 centre (110, -130) radius 4.5
  circle A5 centre (-110, -130) radius 4.5
  circle A6 centre (110, 130) radius 4.5
  circle A7 centre (60, -45) radius 0.8
  circle A8 centre (-60, -30) radius 0.8
  dimension "d405" = 60
  dimension "d406" = 30
  dimension "d407" = 1.6
  measures "d405" horizontal distance of origin A8.centre
  measures "d406" vertical distance of origin A8.centre
  measures "d407" diameter of A8
extrude "CUT-SK-1100-04_M2_RAIL_TAP_A03" cut sketch "SK-1100-04_M2_RAIL_TAP_A03" against normal blind 4 contours A8 bodies 1 in component "CBP-1100_BASE_PLATE"
sketch "SK-1100-04_M2_RAIL_TAP_B03" plane through (0, 12, 0) normal (0, 1, 0) x (0, 0, 1) in component "CBP-1100_BASE_PLATE"
  circle A0 centre (60, -45) radius 0.8
  circle A1 centre (110, 130) radius 4.5
  circle A2 centre (-110, -130) radius 4.5
  circle A3 centre (110, -130) radius 4.5
  circle A4 centre (-110, 130) radius 4.5
  line L0 (49, 74) -> (49, -74)
  line L1 (49, -74) -> (-49, -74)
  line L2 (-49, -74) -> (-49, 74)
  line L3 (-49, 74) -> (49, 74)
  line L4 (130, 150) -> (-130, 150)
  line L5 (-130, 150) -> (-130, -150)
  line L6 (-130, -150) -> (130, -150)
  line L7 (130, -150) -> (130, 150)
  circle A5 centre (-60, -60) radius 0.8
  circle A6 centre (60, -60) radius 0.8
  circle A7 centre (-60, -45) radius 0.8
  circle A8 centre (-60, -30) radius 0.8
  circle A9 centre (60, -30) radius 0.8
  dimension "d410" = 60
  dimension "d411" = 30
  dimension "d412" = 1.6
  measures "d410" horizontal distance of origin A9.centre
  measures "d411" vertical distance of origin A9.centre
  measures "d412" diameter of A9
extrude "CUT-SK-1100-04_M2_RAIL_TAP_B03" cut sketch "SK-1100-04_M2_RAIL_TAP_B03" against normal blind 4 contours A9 bodies 1 in component "CBP-1100_BASE_PLATE"
sketch "SK-1300-02_RAIL_CLEAR_04" plane through (0, 0, 0) normal (0, 1, 0) x (1, 0, 0) in component "CBP-1300_X_RAIL_ALIGNMENT_SHIM"
  circle A0 centre (-15, 0) radius 1.15
  dimension "d415" = 15
  dimension "d416" = 2.3
  constraint horizontal origin A0.centre
  measures "d415" horizontal distance of origin A0.centre
  measures "d416" diameter of A0
extrude "CUT-SK-1300-02_RAIL_CLEAR_04" cut sketch "SK-1300-02_RAIL_CLEAR_04" along normal blind 2 bodies 12 in component "CBP-1300_X_RAIL_ALIGNMENT_SHIM"
sketch "SK-1100-04_M2_RAIL_TAP_A04" plane through (0, 12, 0) normal (0, 1, 0) x (0, 0, 1) in component "CBP-1100_BASE_PLATE"
  circle A0 centre (-60, -30) radius 0.8
  circle A1 centre (-60, -45) radius 0.8
  circle A2 centre (60, -60) radius 0.8
  circle A3 centre (-60, -60) radius 0.8
  line L0 (130, 150) -> (-130, 150)
  line L1 (-130, 150) -> (-130, -150)
  line L2 (-130, -150) -> (130, -150)
  line L3 (130, -150) -> (130, 150)
  line L4 (49, 74) -> (49, -74)
  line L5 (49, -74) -> (-49, -74)
  line L6 (-49, -74) -> (-49, 74)
  line L7 (-49, 74) -> (49, 74)
  circle A4 centre (-110, 130) radius 4.5
  circle A5 centre (110, -130) radius 4.5
  circle A6 centre (-110, -130) radius 4.5
  circle A7 centre (110, 130) radius 4.5
  circle A8 centre (60, -45) radius 0.8
  circle A9 centre (60, -30) radius 0.8
  circle A10 centre (-60, -15) radius 0.8
  dimension "d419" = 60
  dimension "d420" = 15
  dimension "d421" = 1.6
  measures "d419" horizontal distance of origin A10.centre
  measures "d420" vertical distance of origin A10.centre
  measures "d421" diameter of A10